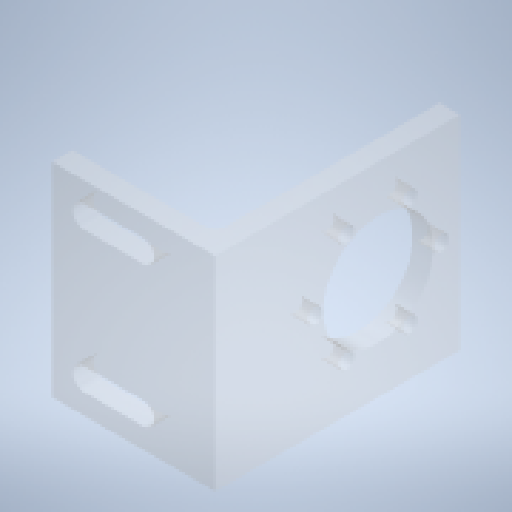
# Autodesk Inventor part: Support moteur
Saved by Autodesk Inventor 2025.3 (Build 293356000, 356)
## iProperties
Created: 2025-04-28
Part Number: Support moteur
Material: PET-Kunststoff
Document SubType Name: Modeling
Designer: karle
Density: 1.541 g/cm^3
Appearance: Polycarbonat - klar
Author: karle
Autodesk Inventor part; units mm, degrees
ref_plane "YZ Plane" through (0, 0, 0) normal (1, 0, 0) x (0, 1, 0)
ref_plane "XZ Plane" through (0, 0, 0) normal (0, 1, 0) x (-1, 0, 0)
ref_plane "XY Plane" through (0, 0, 0) normal (0, 0, 1) x (1, 0, 0)
sketch "Skizze1" plane through (0, 0, 0) normal (0, 0, 1) x (1, 0, 0)
  line L0 (0, 60) -> (0, 0)
  line L1 (0, 0) -> (-40, 0)
  line L2 (-40, 0) -> (-40, 5)
  line L3 (-40, 5) -> (-5, 5)
  line L4 (-5, 5) -> (-5, 60)
  line L5 (-5, 60) -> (0, 60)
  point P0 (-2.5, 60)
  point P1 (-40, 2.5)
  dimension "d0" = 5
  dimension "d1" = 5
  dimension "d2" = 60
  dimension "d3" = 40
  constraints: 12 end point, 5 perpendicular, 2 midpoint, 1 vertical
  measures "d0" distance between parallel lines of L0 L4
  measures "d1" distance between parallel lines of L1 L3
  measures "d2" distance from line of L1 point (-2.5, 60)
  measures "d3" distance from line of L0 point (-40, 2.5)
extrude "Extrusion1" add sketch "Skizze1" against normal blind 50
sketch "Skizze2" plane through (-5, 5, 0) normal (-1, 0, 0) x (0, 0, 1)
  line L0 (0, 55) -> (-50, 55) projected
  line L1 (0, 55) -> (0, 0) projected
  point P0 (0, -5)
  point P1 (-25, 35)
  point P2 (-25, 50.5)
  point P3 (-25, 35)
  point P4 (-38.4234, 42.75)
  point P5 (-25, 35)
  point P6 (-38.4234, 27.25)
  point P7 (-25, 35)
  point P8 (-25, 19.5)
  point P9 (-25, 35)
  point P10 (-11.5766, 27.25)
  point P11 (-25, 35)
  point P12 (-11.5766, 42.75)
  point P13 (-25, 55)
  dimension "d8" = 360
  dimension "d10" = 20
  dimension "d11" = 31
  dimension "d12" = 25
  dimension "d14" = 4.5
  constraints: 2 coincident, 1 midpoint, 11 other
  measures "d10" distance from line of point (-25, 35) L0
  measures "d11" distance of point (-38.423, 42.75) point (-11.577, 27.25)
  measures "d12" distance from line of L1 point (-25, 35)
  measures "d14" distance of point (-25, 55) point (-25, 50.5)
hole "Bohrung1" at (-5, 24.5, -25) at (-5, 32.25, -11.5766) at (-5, 47.75, -11.5766) at (-5, 55.5, -25) at (-5, 47.75, -38.4234) at (-5, 32.25, -38.4234) direction (1, 0, 0) diameter 3.7 end through all
sketch "Skizze3" plane through (-40, 5, 0) normal (0, 1, 0) x (1, 0, 0)
  line L0 (5, 45) -> (25, 45)
  line L1 (25, 45) -> (25, 39.5)
  line L2 (25, 39.5) -> (5, 39.5)
  line L3 (5, 39.5) -> (5, 45)
  line L4 (5, 10.5) -> (25, 10.5)
  line L5 (25, 10.5) -> (25, 5)
  line L6 (25, 5) -> (5, 5)
  line L7 (5, 5) -> (5, 10.5)
  line L8 (0, 50) -> (35, 50) projected
  line L9 (35, 0) -> (0, 0) projected
  line L10 (0, 0) -> (0, 50) projected
  point P0 (40, 0)
  point P1 (17.5, 0)
  point P2 (5, 42.25)
  point P3 (25, 42.25)
  dimension "d22" = 5.5
  dimension "d23" = 5
  dimension "d24" = 5
  dimension "d25" = 5
  dimension "d26" = 20
  constraints: 16 end point, 4 parallel, 3 midpoint, 2 horizontal, 2 perpendicular, 2 point on line, 1 collinear
  measures "d22" distance between parallel lines of L2 L0
  measures "d23" distance between parallel lines of L8 L0
  measures "d24" distance from line of point (17.5, 0) L6
  measures "d25" distance from line of L10 point (5, 42.25)
  measures "d26" horizontal distance of L2.end point (25, 42.25)
extrude "Extrusion2" cut sketch "Skizze3" against normal through all
fillet "Rundung1" radius 2.75 8 edges at (-15, 2.5, -45) (-15, 2.5, -39.5) (-15, 2.5, -5) (-15, 2.5, -10.5) (-35, 2.5, -45) (-35, 2.5, -39.5) (-35, 2.5, -5) (-35, 2.5, -10.5)
sketch "Skizze5" plane through (-5, 5, 0) normal (-1, 0, 0) x (0, 0, 1)
  line L0 (0, 55) -> (-50, 55) projected
  line L1 (0, 55) -> (0, 0) projected
  point P0 (0, -5)
  point P1 (-25, 35)
  dimension "d37" = 20
  dimension "d38" = 25
  measures "d37" distance from line of point (-25, 35) L0
  measures "d38" distance from line of L1 point (-25, 35)
hole "Bohrung3" at (-5, 40, -25) direction (1, 0, 0) diameter 27 end through all
fillet "Rundung2" radius 3 1 edges at (-5, 5, -25)
equation "\"d1\" = d0"
